High Goal (Autodesk Fusion 360 design; units mm, degrees)
part number: 2026-10-17-16-30-18-474
Autodesk Fusion 360 part; units mm, degrees
sketch "Sketch1" plane through (0, 0, 0) normal (0, 0, 1) x (1, 0, 0)
  line L0 (190, 20) -> (-190, 20)
  line L1 (-190, 20) -> (-190, -20)
  line L2 (-190, -20) -> (190, -20)
  line L3 (190, -20) -> (190, 20)
  line L4 (190, 20) -> (-190, -20) construction
  line L5 (-190, 20) -> (190, -20) construction
  dimension "d1" = 380
  dimension "d2" = 40
  constraint horizontal L0
  constraint perpendicular L0 L1
  constraint parallel L0 L2
  constraint parallel L1 L3
  constraint coincident L4 origin
  constraint coincident L5 origin
  measures "d1" distance of L1.end L2.end
  measures "d2" distance of L0.end L1.end
extrude "Extrude1" add sketch "Sketch1" along normal blind 1170
sketch "Sketch2" plane through (0, -20, 0) normal (0, -1, 0) x (1, 0, 0)
  line L0 (-190, 0) -> (190, 0)
  line L1 (190, 0) -> (190, 1170)
  line L2 (190, 1170) -> (-190, 1170)
  line L3 (-190, 1170) -> (-190, 0)
  line L4 (0, 1170) -> (0, 0) construction
  circle A0 centre (0, 980) radius 150
  dimension "d5" = 300
  dimension "d6" = 190
  constraint midpoint L2 L4.start
  constraint coincident L4.end origin
  constraint coincident L4 A0.centre
  measures "d5" diameter of A0
  measures "d6" distance of L2 A0.centre
extrude "Extrude2" cut sketch "Sketch2" against normal up to surface (40 mm away) contours A0
equation "d3 = 1 m + 17 cm"
equation "d6 = 15 cm + 4 cm"
